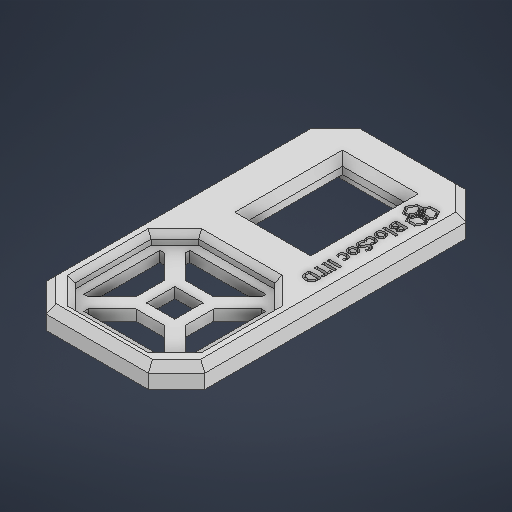
# Autodesk Inventor part: front_pannel_v3
Saved by Autodesk Inventor 2026.2 (Build 302298010, 298A)
## iProperties
Created: 2026-08-06
Part Number: front_pannel_v3
Material: Generic
Document SubType Name: Modeling
Designer: Kugelblitz
Density: 1 g/cm^3
Appearance: Default
Author: Kugelblitz
Autodesk Inventor part; units mm, degrees
ref_plane "YZ Plane" through (0, 0, 0) normal (1, 0, 0) x (0, 1, 0)
ref_plane "XZ Plane" through (0, 0, 0) normal (0, 1, 0) x (-1, 0, 0)
ref_plane "XY Plane" through (0, 0, 0) normal (0, 0, 1) x (1, 0, 0)
sketch "Sketch1" plane through (0, 0, 0) normal (0, 1, 0) x (-1, 0, 0)
  line L0 (22.5, 22) -> (-22.5, 22)
  line L1 (-22.5, 22) -> (-22.5, -68)
  line L2 (-22.5, -68) -> (22.5, -68)
  line L3 (22.5, -68) -> (22.5, 22)
  line L4 (22.5, -23) -> (-22.5, -23)
  line L5 (-22.5, 14) -> (-14.5, 22)
  line L6 (22.5, 14) -> (14.5, 22)
  line L7 (0, -25.7487) -> (0, 24.7487) construction
  line L8 (-24.7487, 0) -> (24.7487, 0) construction
  line L9 (-14.5, -68) -> (-22.5, -60)
  line L10 (22.5, -60) -> (14.5, -68)
  point P0 (0, 0)
  point P1 (15.5, -0.5)
  point P2 (0, -23)
  point P3 (0, 0)
  point P4 (0, -0.5)
  dimension "d3" = 7
  dimension "d11" = 35
  dimension "d14" = 8
  dimension "d15" = 135
  dimension "d16" = 8
  dimension "d21" = 135
  dimension "d22" = 8
  dimension "d23" = 8
  dimension "d68" = 22
  dimension "d69" = 45
  dimension "d70" = 45
  dimension "d71" = 45
  dimension "d72" = 22.5
  dimension "d73" = 22.5
  constraints: 22 end point, 9 point on line, 6 midpoint, 4 perpendicular, 2 parallel, 1 horizontal
  measures "d3" distance from line of point (15.5, -0.5) L3
  measures "d11" distance of L8.start L7.end
  measures "d14" horizontal distance of L5.start L5.end
  measures "d15" angle of L1 L5
  measures "d16" horizontal distance of L6.start L6.end
  measures "d21" angle of L2 L9
  measures "d22" distance from line of L1 L9.start
  measures "d23" distance of L2.end L10.end
  measures "d68" distance from line of L0 point (0, 0)
  measures "d69" distance between parallel lines of L0 L4
  measures "d70" distance between parallel lines of L4 L2
  measures "d71" distance between parallel lines of L3 L1
  measures "d72" distance from line of L3 point (0, -0.5)
  measures "d73" distance from line of L0 point (0, -0.5)
extrude "Extrusion1" add sketch "Sketch1" along normal blind 4 and the other way blind 2 contours L6 L3 L4 L1 L5 L0 | L3 L10 L2 L9 L1 L4
chamfer "Chamfer2" distance 2 angle 45 8 edges at (-22.5, 4, -23) (-18.5, 4, -64) (0, 4, -68) (18.5, 4, -64) (22.5, 4, -23) (18.5, 4, 18) (0, 4, 22) (-18.5, 4, 18)
sketch "Sketch12" plane through (0, 4, 0) normal (0, 1, 0) x (1, 0, 0)
  line L0 (17.5, 17.5) -> (-17.5, 17.5)
  line L1 (-17.5, 17.5) -> (-17.5, -17.5)
  line L2 (-17.5, -17.5) -> (17.5, -17.5)
  line L3 (17.5, -17.5) -> (17.5, 17.5)
  line L4 (17.5, 17.5) -> (-17.5, -17.5) construction
  line L5 (-17.5, 17.5) -> (17.5, -17.5) construction
  line L6 (-28.2843, 0) -> (0, -28.2843)
  line L7 (0, -28.2843) -> (28.2843, 0)
  line L8 (28.2843, 0) -> (0, 28.2843)
  line L9 (0, 28.2843) -> (-28.2843, 0)
  line L10 (-28.2843, 0) -> (28.2843, 0) construction
  line L11 (0, -28.2843) -> (0, 28.2843) construction
  point P0 (0, 0)
  point P1 (-10.7843, 17.5)
  point P2 (-17.5, 10.7843)
  point P3 (-17.5, -10.7843)
  point P4 (-10.7843, -17.5)
  point P5 (10.7843, -17.5)
  point P6 (17.5, -10.7843)
  point P7 (17.5, 10.7843)
  point P8 (10.7843, 17.5)
  dimension "d74" = 35
  dimension "d75" = 35
  dimension "d76" = 40
  dimension "d77" = 40
  constraints: 24 end point, 4 midpoint, 4 parallel, 2 perpendicular, 1 horizontal
  measures "d74" distance of L2.end L1.end
  measures "d75" distance of L1.end L0.end
  measures "d76" distance of L6.start L6.end
  measures "d77" distance of L7.end L6.end
extrude "Extrusion6" cut sketch "Sketch12" against normal blind 3 contours L8 L3 L7 L2 L6 L1 L9 L0
sketch "Sketch13" plane through (0, 1, 0) normal (0, 1, 0) x (1, 0, 0)
  line L0 (-4, 4) -> (4, 4)
  line L1 (4, 4) -> (4, -4)
  line L2 (4, -4) -> (-4, -4)
  line L3 (-4, -4) -> (-4, 4)
  line L4 (-4, 4) -> (4, -4) construction
  line L5 (4, 4) -> (-4, -4) construction
  line L6 (4, -7) -> (-4, -7)
  line L7 (-4, -7) -> (-10.7843, -13.7843)
  line L8 (10.7843, -13.7843) -> (4, -7)
  line L9 (17.5, -10.7843) -> (10.7843, -17.5) projected
  line L10 (10.7843, -13.7843) -> (10.7843, -15)
  line L11 (10.7843, -15) -> (-10.7843, -15)
  line L12 (-10.7843, -15) -> (-10.7843, -13.7843)
  line L13 (10.7843, -17.5) -> (-10.7843, -17.5) projected
  line L14 (7, 4) -> (7, -4)
  line L15 (7, -4) -> (13.7843, -10.7843)
  line L16 (15, -10.7843) -> (13.7843, -10.7843)
  line L17 (15, 10.7843) -> (15, -10.7843)
  line L18 (13.7843, 10.7843) -> (15, 10.7843)
  line L19 (13.7843, 10.7843) -> (7, 4)
  line L20 (-4, 7) -> (4, 7)
  line L21 (4, 7) -> (10.7843, 13.7843)
  line L22 (10.7843, 15) -> (10.7843, 13.7843)
  line L23 (-10.7843, 15) -> (10.7843, 15)
  line L24 (-10.7843, 13.7843) -> (-10.7843, 15)
  line L25 (-10.7843, 13.7843) -> (-4, 7)
  line L26 (-7, -4) -> (-7, 4)
  line L27 (-7, 4) -> (-13.7843, 10.7843)
  line L28 (-15, 10.7843) -> (-13.7843, 10.7843)
  line L29 (-15, -10.7843) -> (-15, 10.7843)
  line L30 (-13.7843, -10.7843) -> (-15, -10.7843)
  line L31 (-13.7843, -10.7843) -> (-7, -4)
  point P0 (0, 0)
  point P1 (0, -4)
  point P2 (0, -7)
  point P3 (7, 0)
  point P4 (0, 7)
  point P5 (-7, 0)
  dimension "d80" = 8
  dimension "d81" = 8
  dimension "d82" = 8
  dimension "d83" = 0
  dimension "d84" = 3
  dimension "d85" = 8
  dimension "d86" = 0
  dimension "d87" = 0
  dimension "d90" = 360
  constraints: 60 end point, 5 perpendicular, 4 midpoint, 2 horizontal, 2 parallel, 1 vertical, 53 other
  measures "d80" distance of L1.end L2.end
  measures "d81" distance of L0.end L1.end
  measures "d82" distance of L6.start L6.end
  measures "d83" horizontal distance of point (0, -4) point (0, -7)
  measures "d84" distance between parallel lines of L6 L2
  measures "d85" distance between parallel lines of L6 L11
  measures "d86" horizontal distance of L9.end L10.end
  measures "d87" horizontal distance of L13.end L11.end
extrude "Extrusion7" cut sketch "Sketch13" against normal through all
sketch "Sketch14" plane through (0, 4, 0) normal (0, 1, 0) x (1, 0, 0)
  line L0 (8.75, 56.25) -> (-8.75, 56.25)
  line L1 (-8.75, 56.25) -> (-8.75, 29.75)
  line L2 (-8.75, 29.75) -> (8.75, 29.75)
  line L3 (8.75, 29.75) -> (8.75, 56.25)
  line L4 (-13.6716, 66) -> (13.6716, 66) projected
  line L5 (0, 66) -> (0, 17.5)
  line L6 (-10.7843, 17.5) -> (10.7843, 17.5) projected
  point P0 (0, 0)
  point P1 (0, 66)
  point P2 (0, 56.25)
  point P3 (8.75, 43)
  point P4 (0, 66)
  dimension "d94" = 17.5
  dimension "d95" = 26.5
  dimension "d96" = 0
  dimension "d97" = 23
  dimension "d98" = 0
  constraints: 10 end point, 6 midpoint, 2 parallel, 1 horizontal, 1 perpendicular, 1 vertical
  measures "d94" distance of L1.end L2.end
  measures "d95" distance of L2.end L0.start
  measures "d96" horizontal distance of point (0, 66) point (0, 56.25)
  measures "d97" distance from line of L4 point (8.75, 43)
  measures "d98" distance from line of point (0, 66) L5
extrude "Extrusion8" cut sketch "Sketch14" against normal blind 10
chamfer "Chamfer4" distance 1.5 angle 45 8 edges at (17.5, 4, 0) (14.1421, 4, -14.1421) (0, 4, -17.5) (-14.1421, 4, -14.1421) (-17.5, 4, 0) (-14.1421, 4, 14.1421) (0, 4, 17.5) (14.1421, 4, 14.1421)
chamfer "Chamfer5" distance 2 angle 45 4 edges at (8.75, 4, -43) (0, 4, -56.25) (-8.75, 4, -43) (0, 4, -29.75)
sketch "Sketch15" plane through (0, -2, 0) normal (0, -1, 0) x (1, 0, 0)
  line L0 (14, -29) -> (-14, -29)
  line L1 (-14, -29) -> (-14, -57)
  line L2 (-14, -57) -> (14, -57)
  line L3 (14, -57) -> (14, -29)
  line L4 (8.75, -56.25) -> (-8.75, -56.25) projected
  line L5 (8.75, -29.75) -> (8.75, -56.25) projected
  point P0 (0, 0)
  point P1 (0, -57)
  point P2 (0, -56.25)
  point P3 (8.75, -43)
  point P4 (14, -43)
  dimension "d107" = 0
  dimension "d108" = 0
  dimension "d109" = 28
  dimension "d110" = 28
  constraints: 8 end point, 4 midpoint, 2 parallel, 1 horizontal, 1 perpendicular
  measures "d107" horizontal distance of point (0, -57) point (0, -56.25)
  measures "d108" vertical distance of point (8.75, -43) point (14, -43)
  measures "d109" distance of L2.end L0.start
  measures "d110" distance of L1.end L2.end
extrude "Extrusion9" cut sketch "Sketch15" against normal blind 2
sketch "Sketch17" plane through (0, 4, 0) normal (0, 1, 0) x (1, 0, 0)
  line L0 (17.9346, 48.8212) -> (17.9346, 19.4643) construction
  line L1 (17.9346, 19.4643) -> (10.0297, 19.4643) construction
  line L2 (10.0297, 19.4643) -> (10.0297, 48.8212) construction
  line L3 (10.0297, 48.8212) -> (17.9346, 48.8212) construction
  line L4 (20.5, 59.1716) -> (20.5, -13.1716) projected
  line L5 (15.6198, 52.5504) -> (14.3698, 54.7154)
  line L6 (14.3698, 54.7154) -> (15.6198, 56.8805)
  line L7 (15.6198, 56.8805) -> (18.1198, 56.8805)
  line L8 (18.1198, 56.8805) -> (19.3698, 54.7154)
  line L9 (19.3698, 54.7154) -> (18.1198, 52.5504)
  line L10 (18.1198, 52.5504) -> (15.6198, 52.5504)
  line L11 (15.9662, 56.2805) -> (17.7734, 56.2805)
  line L12 (17.7734, 56.2805) -> (18.677, 54.7154)
  line L13 (18.677, 54.7154) -> (17.7734, 53.1504)
  line L14 (17.7734, 53.1504) -> (15.9662, 53.1504)
  line L15 (15.9662, 53.1504) -> (15.0627, 54.7154)
  line L16 (15.0627, 54.7154) -> (15.9662, 56.2805)
  line L17 (15.6198, 49.8203) -> (14.3698, 51.9853)
  line L18 (14.3698, 51.9853) -> (15.6198, 54.1504)
  line L19 (15.6198, 54.1504) -> (18.1198, 54.1504)
  line L20 (18.1198, 54.1504) -> (19.3698, 51.9853)
  line L21 (19.3698, 51.9853) -> (18.1198, 49.8203)
  line L22 (18.1198, 49.8203) -> (15.6198, 49.8203)
  line L23 (15.9662, 53.5504) -> (17.7734, 53.5504)
  line L24 (17.7734, 53.5504) -> (18.677, 51.9853)
  line L25 (18.677, 51.9853) -> (17.7734, 50.4203)
  line L26 (17.7734, 50.4203) -> (15.9662, 50.4203)
  line L27 (15.9662, 50.4203) -> (15.0627, 51.9853)
  line L28 (15.0627, 51.9853) -> (15.9662, 53.5504)
  line L29 (13.2555, 51.1853) -> (12.0055, 53.3504)
  line L30 (12.0055, 53.3504) -> (13.2555, 55.5154)
  line L31 (13.2555, 55.5154) -> (15.7555, 55.5154)
  line L32 (15.7555, 55.5154) -> (17.0055, 53.3504)
  line L33 (17.0055, 53.3504) -> (15.7555, 51.1853)
  line L34 (15.7555, 51.1853) -> (13.2555, 51.1853)
  line L35 (13.6019, 54.9154) -> (15.4091, 54.9154)
  line L36 (15.4091, 54.9154) -> (16.3127, 53.3504)
  line L37 (16.3127, 53.3504) -> (15.4091, 51.7853)
  line L38 (15.4091, 51.7853) -> (13.6019, 51.7853)
  line L39 (13.6019, 51.7853) -> (12.6983, 53.3504)
  line L40 (12.6983, 53.3504) -> (13.6019, 54.9154)
  spline S0 degree 2 poles (15.2299, 45.9161) (15.0426, 45.9161) (14.7403, 46.0179) (14.5102, 46.1987) (14.3426, 46.4485) (14.2375, 46.7508) (14.1849, 47.0926) (14.1849, 47.3029) knots 0 0 0 1 2 3 4 5 6 6 6
  line L41 (14.1849, 47.3029) -> (14.1849, 48.2297)
  spline S1 degree 2 poles (14.1849, 48.2297) (14.1849, 48.3184) (14.29, 48.44) (14.4083, 48.44) knots 0 0 0 1 2 2 2
  line L42 (14.4083, 48.44) -> (17.445, 48.44)
  spline S2 degree 2 poles (17.445, 48.44) (17.5633, 48.44) (17.6684, 48.3184) (17.6684, 48.2297) knots 0 0 0 1 2 2 2
  line L43 (17.6684, 48.2297) -> (17.6684, 47.3555)
  spline S3 degree 2 poles (17.6684, 47.3555) (17.6684, 47.0334) (17.56, 46.5898) (17.3431, 46.2841) (17.0079, 46.1231) (16.7811, 46.1231) knots 0 0 0 1 2 3 4 4 4
  spline S4 degree 2 poles (16.7811, 46.1231) (16.6562, 46.1231) (16.4328, 46.1888) (16.2487, 46.3104) (16.1074, 46.4912) (16.0647, 46.6095) knots 0 0 0 1 2 3 4 4 4
  spline S5 degree 2 poles (16.0647, 46.6095) (16.0384, 46.4583) (15.9037, 46.2086) (15.6933, 46.0245) (15.4074, 45.9161) (15.2299, 45.9161) knots 0 0 0 1 2 3 4 4 4
  spline S6 degree 2 poles (15.2069, 46.6522) (15.3253, 46.6522) (15.5159, 46.7344) (15.6473, 46.8888) (15.7163, 47.132) (15.7163, 47.3259) knots 0 0 0 1 2 3 4 4 4
  line L44 (15.7163, 47.3259) -> (15.7163, 47.7466)
  line L45 (15.7163, 47.7466) -> (14.7271, 47.7466)
  line L46 (14.7271, 47.7466) -> (14.7271, 47.2339)
  spline S7 degree 2 poles (14.7271, 47.2339) (14.7271, 47.086) (14.7896, 46.8855) (14.9112, 46.7344) (15.0886, 46.6522) (15.2069, 46.6522) knots 0 0 0 1 2 3 4 4 4
  spline S8 degree 2 poles (16.6957, 46.8297) (16.8008, 46.8297) (16.9684, 46.8954) (17.0802, 47.0236) (17.1393, 47.2208) (17.1393, 47.3884) knots 0 0 0 1 2 3 4 4 4
  line L47 (17.1393, 47.3884) -> (17.1393, 47.7466)
  line L48 (17.1393, 47.7466) -> (16.2323, 47.7466)
  line L49 (16.2323, 47.7466) -> (16.2323, 47.3489)
  spline S9 degree 2 poles (16.2323, 47.3489) (16.2323, 47.1945) (16.3046, 47.0104) (16.4328, 46.8888) (16.6037, 46.8297) (16.6957, 46.8297) knots 0 0 0 1 2 3 4 4 4
  spline S10 degree 2 poles (14.2769, 44.7132) (14.2506, 44.7132) (14.2079, 44.7461) (14.1816, 44.825) (14.1684, 44.9532) (14.1684, 45.0517) knots 0 0 0 1 2 3 4 4 4
  spline S11 degree 2 poles (14.1684, 45.0517) (14.1684, 45.1503) (14.1816, 45.2785) (14.2079, 45.3574) (14.2506, 45.3902) (14.2769, 45.3902) knots 0 0 0 1 2 3 4 4 4
  line L50 (14.2769, 45.3902) -> (17.8196, 45.3902)
  spline S12 degree 2 poles (17.8196, 45.3902) (17.8459, 45.3902) (17.8886, 45.3574) (17.9182, 45.2785) (17.9346, 45.1503) (17.9346, 45.0517) knots 0 0 0 1 2 3 4 4 4
  spline S13 degree 2 poles (17.9346, 45.0517) (17.9346, 44.9532) (17.9182, 44.825) (17.8886, 44.7461) (17.8459, 44.7132) (17.8196, 44.7132) knots 0 0 0 1 2 3 4 4 4
  line L51 (17.8196, 44.7132) -> (14.2769, 44.7132)
  spline S14 degree 2 poles (15.4994, 41.6076) (15.1938, 41.6076) (14.6877, 41.7686) (14.3229, 42.0973) (14.1224, 42.5935) (14.1224, 42.9255) knots 0 0 0 1 2 3 4 4 4
  spline S15 degree 2 poles (14.1224, 42.9255) (14.1224, 43.2442) (14.2999, 43.7175) (14.6384, 44.0297) (15.1346, 44.1809) (15.4534, 44.1809) knots 0 0 0 1 2 3 4 4 4
  spline S16 degree 2 poles (15.4534, 44.1809) (15.7591, 44.1809) (16.2684, 44.0165) (16.6299, 43.6879) (16.8304, 43.1949) (16.8304, 42.863) knots 0 0 0 1 2 3 4 4 4
  spline S17 degree 2 poles (16.8304, 42.863) (16.8304, 42.5409) (16.6562, 42.0677) (16.3177, 41.7588) (15.8215, 41.6076) (15.4994, 41.6076) knots 0 0 0 1 2 3 4 4 4
  spline S18 degree 2 poles (15.4731, 42.3043) (15.6506, 42.3043) (15.9497, 42.3602) (16.1699, 42.4949) (16.2947, 42.7184) (16.2947, 42.8893) knots 0 0 0 1 2 3 4 4 4
  spline S19 degree 2 poles (16.2947, 42.8893) (16.2947, 43.0405) (16.183, 43.2672) (15.9727, 43.4118) (15.6736, 43.4841) (15.483, 43.4841) knots 0 0 0 1 2 3 4 4 4
  spline S20 degree 2 poles (15.483, 43.4841) (15.3055, 43.4841) (15.0065, 43.425) (14.7863, 43.2935) (14.6647, 43.0668) (14.6647, 42.8992) knots 0 0 0 1 2 3 4 4 4
  spline S21 degree 2 poles (14.6647, 42.8992) (14.6647, 42.7447) (14.7764, 42.5212) (14.9835, 42.3733) (15.2825, 42.3043) (15.4731, 42.3043) knots 0 0 0 1 2 3 4 4 4
  spline S22 degree 2 poles (14.6581, 39.2546) (14.5891, 39.2546) (14.4938, 39.2611) (14.4281, 39.2776) (14.3886, 39.294) (14.3262, 39.3597) (14.2375, 39.5142) (14.1684, 39.7147) (14.1257, 39.948) (14.1257, 40.0729) knots 0 0 0 1 2 3 4 5 6 7 8 8 8
  spline S23 degree 2 poles (14.1257, 40.0729) (14.1257, 40.3489) (14.2966, 40.7794) (14.6351, 41.0686) (15.1182, 41.2165) (15.4337, 41.2165) knots 0 0 0 1 2 3 4 4 4
  spline S24 degree 2 poles (15.4337, 41.2165) (15.7919, 41.2165) (16.3177, 41.0358) (16.6628, 40.7137) (16.8304, 40.2733) (16.8304, 40.0071) knots 0 0 0 1 2 3 4 4 4
  spline S25 degree 2 poles (16.8304, 40.0071) (16.8304, 39.902) (16.791, 39.6917) (16.7285, 39.5142) (16.6464, 39.3696) (16.5872, 39.3104) (16.5478, 39.2874) (16.4821, 39.2743) (16.3868, 39.2644) (16.321, 39.2644) knots 0 0 0 1 2 3 4 5 6 7 8 8 8
  spline S26 degree 2 poles (16.321, 39.2644) (16.1633, 39.2644) (16.0384, 39.3203) (16.0384, 39.363) knots 0 0 0 1 2 2 2
  spline S27 degree 2 poles (16.0384, 39.363) (16.0384, 39.409) (16.114, 39.5109) (16.206, 39.6489) (16.2816, 39.8428) (16.2816, 39.9776) knots 0 0 0 1 2 3 4 4 4
  spline S28 degree 2 poles (16.2816, 39.9776) (16.2816, 40.2438) (15.8741, 40.5231) (15.4797, 40.5231) knots 0 0 0 1 2 2 2
  spline S29 degree 2 poles (15.4797, 40.5231) (15.2858, 40.5231) (14.99, 40.4541) (14.7896, 40.3161) (14.691, 40.109) (14.691, 39.971) knots 0 0 0 1 2 3 4 4 4
  spline S30 degree 2 poles (14.691, 39.971) (14.691, 39.8297) (14.7731, 39.6292) (14.8783, 39.478) (14.9605, 39.3762) (14.9605, 39.34) knots 0 0 0 1 2 3 4 4 4
  spline S31 degree 2 poles (14.9605, 39.34) (14.9605, 39.317) (14.9342, 39.2841) (14.8619, 39.2644) (14.7468, 39.2546) (14.6581, 39.2546) knots 0 0 0 1 2 3 4 4 4
  spline S32 degree 2 poles (15.2299, 36.6583) (14.9539, 36.6583) (14.5398, 36.8621) (14.2637, 37.2137) (14.1224, 37.6804) (14.1224, 37.9466) knots 0 0 0 1 2 3 4 4 4
  spline S33 degree 2 poles (14.1224, 37.9466) (14.1224, 38.1273) (14.1816, 38.4363) (14.267, 38.6729) (14.3591, 38.8339) (14.4281, 38.9029) (14.5595, 38.9325) (14.6844, 38.9325) knots 0 0 0 1 2 3 4 5 6 6 6
  spline S34 degree 2 poles (14.6844, 38.9325) (14.7666, 38.9325) (14.8816, 38.9226) (14.9506, 38.8963) (14.9802, 38.8569) (14.9802, 38.8306) knots 0 0 0 1 2 3 4 4 4
  spline S35 degree 2 poles (14.9802, 38.8306) (14.9802, 38.7912) (14.8914, 38.6564) (14.783, 38.4395) (14.6943, 38.1405) (14.6943, 37.9466) knots 0 0 0 1 2 3 4 4 4
  spline S36 degree 2 poles (14.6943, 37.9466) (14.6943, 37.8151) (14.7567, 37.6114) (14.8684, 37.4701) (15.036, 37.3945) (15.1379, 37.3945) knots 0 0 0 1 2 3 4 4 4
  spline S37 degree 2 poles (15.1379, 37.3945) (15.2562, 37.3945) (15.4271, 37.5226) (15.5586, 37.7297) (15.6736, 37.9926) (15.8018, 38.2752) (15.9661, 38.5381) (16.1961, 38.7452) (16.5083, 38.8733) (16.7253, 38.8733) knots 0 0 0 1 2 3 4 5 6 7 8 8 8
  spline S38 degree 2 poles (16.7253, 38.8733) (16.9783, 38.8733) (17.3562, 38.686) (17.606, 38.3738) (17.7309, 37.9433) (17.7309, 37.7034) knots 0 0 0 1 2 3 4 4 4
  spline S39 degree 2 poles (17.7309, 37.7034) (17.7309, 37.5818) (17.6947, 37.332) (17.629, 37.1184) (17.5468, 36.9508) (17.4943, 36.8949) (17.4581, 36.8785) (17.3957, 36.8654) (17.3004, 36.8588) (17.2314, 36.8588) knots 0 0 0 1 2 3 4 5 6 7 8 8 8
  spline S40 degree 2 poles (17.2314, 36.8588) (17.1525, 36.8588) (17.044, 36.8654) (16.975, 36.8851) (16.9422, 36.9212) (16.9422, 36.9508) knots 0 0 0 1 2 3 4 4 4
  spline S41 degree 2 poles (16.9422, 36.9508) (16.9422, 36.9804) (17.0177, 37.1086) (17.1065, 37.2992) (17.1788, 37.5456) (17.1788, 37.6935) knots 0 0 0 1 2 3 4 4 4
  spline S42 degree 2 poles (17.1788, 37.6935) (17.1788, 37.8086) (17.1229, 37.9827) (17.021, 38.0978) (16.883, 38.1536) (16.8041, 38.1536) knots 0 0 0 1 2 3 4 4 4
  spline S43 degree 2 poles (16.8041, 38.1536) (16.6891, 38.1536) (16.5182, 38.0287) (16.3868, 37.8151) (16.2717, 37.5456) (16.1436, 37.2663) (15.9792, 36.9968) (15.7492, 36.7865) (15.4403, 36.6583) (15.2299, 36.6583) knots 0 0 0 1 2 3 4 5 6 7 8 8 8
  spline S44 degree 2 poles (15.4994, 33.7302) (15.1938, 33.7302) (14.6877, 33.8912) (14.3229, 34.2198) (14.1224, 34.7161) (14.1224, 35.048) knots 0 0 0 1 2 3 4 4 4
  spline S45 degree 2 poles (14.1224, 35.048) (14.1224, 35.3668) (14.2999, 35.84) (14.6384, 36.1522) (15.1346, 36.3034) (15.4534, 36.3034) knots 0 0 0 1 2 3 4 4 4
  spline S46 degree 2 poles (15.4534, 36.3034) (15.7591, 36.3034) (16.2684, 36.1391) (16.6299, 35.8104) (16.8304, 35.3175) (16.8304, 34.9855) knots 0 0 0 1 2 3 4 4 4
  spline S47 degree 2 poles (16.8304, 34.9855) (16.8304, 34.6635) (16.6562, 34.1902) (16.3177, 33.8813) (15.8215, 33.7302) (15.4994, 33.7302) knots 0 0 0 1 2 3 4 4 4
  spline S48 degree 2 poles (15.4731, 34.4269) (15.6506, 34.4269) (15.9497, 34.4827) (16.1699, 34.6175) (16.2947, 34.8409) (16.2947, 35.0118) knots 0 0 0 1 2 3 4 4 4
  spline S49 degree 2 poles (16.2947, 35.0118) (16.2947, 35.163) (16.183, 35.3898) (15.9727, 35.5344) (15.6736, 35.6067) (15.483, 35.6067) knots 0 0 0 1 2 3 4 4 4
  spline S50 degree 2 poles (15.483, 35.6067) (15.3055, 35.6067) (15.0065, 35.5475) (14.7863, 35.4161) (14.6647, 35.1893) (14.6647, 35.0217) knots 0 0 0 1 2 3 4 4 4
  spline S51 degree 2 poles (14.6647, 35.0217) (14.6647, 34.8672) (14.7764, 34.6438) (14.9835, 34.4959) (15.2825, 34.4269) (15.4731, 34.4269) knots 0 0 0 1 2 3 4 4 4
  spline S52 degree 2 poles (14.6581, 31.3771) (14.5891, 31.3771) (14.4938, 31.3837) (14.4281, 31.4001) (14.3886, 31.4165) (14.3262, 31.4823) (14.2375, 31.6367) (14.1684, 31.8372) (14.1257, 32.0705) (14.1257, 32.1954) knots 0 0 0 1 2 3 4 5 6 7 8 8 8
  spline S53 degree 2 poles (14.1257, 32.1954) (14.1257, 32.4715) (14.2966, 32.902) (14.6351, 33.1912) (15.1182, 33.3391) (15.4337, 33.3391) knots 0 0 0 1 2 3 4 4 4
  spline S54 degree 2 poles (15.4337, 33.3391) (15.7919, 33.3391) (16.3177, 33.1583) (16.6628, 32.8363) (16.8304, 32.3959) (16.8304, 32.1297) knots 0 0 0 1 2 3 4 4 4
  spline S55 degree 2 poles (16.8304, 32.1297) (16.8304, 32.0245) (16.791, 31.8142) (16.7285, 31.6367) (16.6464, 31.4921) (16.5872, 31.433) (16.5478, 31.41) (16.4821, 31.3968) (16.3868, 31.387) (16.321, 31.387) knots 0 0 0 1 2 3 4 5 6 7 8 8 8
  spline S56 degree 2 poles (16.321, 31.387) (16.1633, 31.387) (16.0384, 31.4428) (16.0384, 31.4855) knots 0 0 0 1 2 2 2
  spline S57 degree 2 poles (16.0384, 31.4855) (16.0384, 31.5316) (16.114, 31.6334) (16.206, 31.7715) (16.2816, 31.9654) (16.2816, 32.1001) knots 0 0 0 1 2 3 4 4 4
  spline S58 degree 2 poles (16.2816, 32.1001) (16.2816, 32.3663) (15.8741, 32.6456) (15.4797, 32.6456) knots 0 0 0 1 2 2 2
  spline S59 degree 2 poles (15.4797, 32.6456) (15.2858, 32.6456) (14.99, 32.5766) (14.7896, 32.4386) (14.691, 32.2316) (14.691, 32.0935) knots 0 0 0 1 2 3 4 4 4
  spline S60 degree 2 poles (14.691, 32.0935) (14.691, 31.9522) (14.7731, 31.7517) (14.8783, 31.6006) (14.9605, 31.4987) (14.9605, 31.4625) knots 0 0 0 1 2 3 4 4 4
  spline S61 degree 2 poles (14.9605, 31.4625) (14.9605, 31.4395) (14.9342, 31.4067) (14.8619, 31.387) (14.7468, 31.3771) (14.6581, 31.3771) knots 0 0 0 1 2 3 4 4 4
  spline S62 degree 2 poles (14.2802, 28.8893) (14.2539, 28.8893) (14.2112, 28.9255) (14.1849, 29.0043) (14.1684, 29.1391) (14.1684, 29.2442) knots 0 0 0 1 2 3 4 4 4
  spline S63 degree 2 poles (14.1684, 29.2442) (14.1684, 29.3461) (14.1849, 29.4841) (14.2112, 29.563) (14.2539, 29.5992) (14.2802, 29.5992) knots 0 0 0 1 2 3 4 4 4
  line L52 (14.2802, 29.5992) -> (17.5731, 29.5992)
  spline S64 degree 2 poles (17.5731, 29.5992) (17.5994, 29.5992) (17.6422, 29.563) (17.6684, 29.4809) (17.6849, 29.3461) (17.6849, 29.2442) knots 0 0 0 1 2 3 4 4 4
  spline S65 degree 2 poles (17.6849, 29.2442) (17.6849, 29.1391) (17.6684, 29.0043) (17.6422, 28.9255) (17.5994, 28.8893) (17.5731, 28.8893) knots 0 0 0 1 2 3 4 4 4
  line L53 (17.5731, 28.8893) -> (14.2802, 28.8893)
  spline S66 degree 2 poles (14.2802, 27.4203) (14.2539, 27.4203) (14.2112, 27.4564) (14.1849, 27.5353) (14.1684, 27.6701) (14.1684, 27.7752) knots 0 0 0 1 2 3 4 4 4
  spline S67 degree 2 poles (14.1684, 27.7752) (14.1684, 27.8771) (14.1849, 28.0151) (14.2112, 28.094) (14.2539, 28.1302) (14.2802, 28.1302) knots 0 0 0 1 2 3 4 4 4
  line L54 (14.2802, 28.1302) -> (17.5731, 28.1302)
  spline S68 degree 2 poles (17.5731, 28.1302) (17.5994, 28.1302) (17.6422, 28.094) (17.6684, 28.0118) (17.6849, 27.8771) (17.6849, 27.7752) knots 0 0 0 1 2 3 4 4 4
  spline S69 degree 2 poles (17.6849, 27.7752) (17.6849, 27.6701) (17.6684, 27.5353) (17.6422, 27.4564) (17.5994, 27.4203) (17.5731, 27.4203) knots 0 0 0 1 2 3 4 4 4
  line L55 (17.5731, 27.4203) -> (14.2802, 27.4203)
  spline S70 degree 2 poles (17.3792, 24.3475) (17.3004, 24.3475) (17.1886, 24.3607) (17.1229, 24.387) (17.09, 24.4297) (17.09, 24.4527) knots 0 0 0 1 2 3 4 4 4
  line L56 (17.09, 24.4527) -> (17.09, 25.3236)
  line L57 (17.09, 25.3236) -> (14.2802, 25.3236)
  spline S71 degree 2 poles (14.2802, 25.3236) (14.2539, 25.3236) (14.2112, 25.3597) (14.1849, 25.4386) (14.1684, 25.5766) (14.1684, 25.6785) knots 0 0 0 1 2 3 4 4 4
  spline S72 degree 2 poles (14.1684, 25.6785) (14.1684, 25.7804) (14.1849, 25.9184) (14.2112, 25.9973) (14.2539, 26.0334) (14.2802, 26.0334) knots 0 0 0 1 2 3 4 4 4
  line L58 (14.2802, 26.0334) -> (17.09, 26.0334)
  line L59 (17.09, 26.0334) -> (17.09, 26.9043)
  spline S73 degree 2 poles (17.09, 26.9043) (17.09, 26.9306) (17.1229, 26.9701) (17.1886, 26.9963) (17.3004, 27.0095) (17.3792, 27.0095) knots 0 0 0 1 2 3 4 4 4
  spline S74 degree 2 poles (17.3792, 27.0095) (17.4581, 27.0095) (17.5731, 26.9963) (17.6389, 26.9701) (17.6684, 26.9306) (17.6684, 26.9043) knots 0 0 0 1 2 3 4 4 4
  line L60 (17.6684, 26.9043) -> (17.6684, 24.4527)
  spline S75 degree 2 poles (17.6684, 24.4527) (17.6684, 24.4297) (17.6389, 24.387) (17.5731, 24.3607) (17.4581, 24.3475) (17.3792, 24.3475) knots 0 0 0 1 2 3 4 4 4
  spline S76 degree 2 poles (15.9792, 21.0348) (15.4994, 21.0348) (14.8191, 21.2846) (14.3853, 21.7546) (14.1849, 22.425) (14.1849, 22.8884) knots 0 0 0 1 2 3 4 4 4
  line L61 (14.1849, 22.8884) -> (14.1849, 23.7198)
  spline S77 degree 2 poles (14.1849, 23.7198) (14.1849, 23.8086) (14.29, 23.9302) (14.4083, 23.9302) knots 0 0 0 1 2 2 2
  line L62 (14.4083, 23.9302) -> (17.445, 23.9302)
  spline S78 degree 2 poles (17.445, 23.9302) (17.5633, 23.9302) (17.6684, 23.8086) (17.6684, 23.7198) knots 0 0 0 1 2 2 2
  line L63 (17.6684, 23.7198) -> (17.6684, 22.8259)
  spline S79 degree 2 poles (17.6684, 22.8259) (17.6684, 22.3593) (17.4515, 21.7118) (17.021, 21.2649) (16.3933, 21.0348) (15.9792, 21.0348) knots 0 0 0 1 2 3 4 4 4
  spline S80 degree 2 poles (15.953, 21.7677) (16.1994, 21.7677) (16.6267, 21.8827) (16.9389, 22.1391) (17.113, 22.54) (17.113, 22.8654) knots 0 0 0 1 2 3 4 4 4
  line L64 (17.113, 22.8654) -> (17.113, 23.2236)
  line L65 (17.113, 23.2236) -> (14.7436, 23.2236)
  line L66 (14.7436, 23.2236) -> (14.7436, 22.8555)
  spline S81 degree 2 poles (14.7436, 22.8555) (14.7436, 22.563) (14.8947, 22.1654) (15.1971, 21.8992) (15.6506, 21.7677) (15.953, 21.7677) knots 0 0 0 1 2 3 4 4 4
  point P0 (0, 0)
  point P1 (16.8698, 54.7154)
  point P2 (16.8698, 54.7154)
  point P3 (16.8698, 51.9853)
  point P4 (16.8698, 51.9853)
  point P5 (16.8698, 54.1504)
  point P6 (16.8698, 52.5504)
  point P7 (14.5055, 53.3504)
  point P8 (14.5055, 53.3504)
  point P9 (14.5055, 50.1125)
  point P10 (14.5055, 51.1853)
  point P11 (18.2353, 52.7504)
  point P12 (15.5245, 51.1853)
  point P13 (16.5436, 52.5504)
  point P14 (17.8889, 53.3504)
  point P15 (16.89, 53.1504)
  point P16 (16.89, 53.5504)
  point P17 (15.5044, 53.9504)
  point P18 (15.1781, 54.9154)
  point P19 (15.8508, 54.1504)
  point P20 (15.5044, 52.7504)
  point P21 (15.8508, 52.5504)
  point P22 (15.1781, 51.7853)
  point P23 (15.158, 53.3504)
  point P24 (14.4853, 51.7853)
  point P25 (14.4853, 54.9154)
  point P26 (18.5817, 53.3504)
  point P27 (14.8317, 55.5154)
  point P28 (14.8317, 51.1853)
  point P29 (15.8508, 53.3504)
  point P30 (16.1972, 53.5504)
  point P31 (16.1972, 53.1504)
  point P32 (18.2353, 53.9504)
  point P33 (16.5436, 54.1504)
  point P34 (15.5245, 55.5154)
  dimension "d3" = 7
  dimension "d11" = 35
  dimension "d14" = 8
  dimension "d15" = 135
  dimension "d16" = 8
  dimension "d21" = 135
  dimension "d22" = 8
  dimension "d23" = 8
  dimension "d68" = 22
  dimension "d69" = 45
  dimension "d70" = 45
  dimension "d71" = 45
  dimension "d72" = 22.5
  dimension "d73" = 22.5
  dimension "d113" = 180
  dimension "d114" = 0
  dimension "d115" = 0
  dimension "d116" = 0.6
  dimension "d117" = 2.5
  dimension "d118" = 0
  dimension "d119" = 0
  dimension "d120" = 0.6
  dimension "d121" = 2.5
  dimension "d122" = 0.4
  dimension "d123" = 0
  dimension "d124" = 0
  dimension "d125" = 0
  dimension "d126" = 0.6
  dimension "d127" = 2.5
  dimension "d129" = 0
  dimension "d131" = 0.4
  dimension "d132" = 0.4
  constraints: 72 end point, 5 parallel, 3 midpoint, 80 other
  measures "d113" angle of L4 L2
  measures "d114" distance of point (16.87, 54.715) point (16.87, 54.715)
  measures "d115" distance of point (16.87, 54.715) point (16.87, 54.715)
  measures "d116" distance between parallel lines of L10 L14
  measures "d117" distance of L9.end L5.start
  measures "d118" distance of point (16.87, 51.985) point (16.87, 51.985)
  measures "d119" distance of point (16.87, 51.985) point (16.87, 51.985)
  measures "d120" distance between parallel lines of L22 L26
  measures "d121" distance of L22.start L17.start
  measures "d122" distance between parallel lines of L14 L23
  measures "d123" horizontal distance of point (16.87, 54.15) point (16.87, 52.55)
  measures "d124" distance of point (14.505, 53.35) point (14.505, 53.35)
  measures "d125" distance of point (14.505, 53.35) point (14.505, 53.35)
  measures "d126" distance between parallel lines of L34 L38
  measures "d127" distance of L33.end L29.start
  measures "d129" horizontal distance of point (14.505, 50.112) point (14.505, 51.185)
  measures "d131" distance between parallel lines of L15 L36
  measures "d132" distance between parallel lines of L37 L28
extrude "Extrusion10" cut sketch "Sketch17" against normal blind 1 contours L5 L28 L15 L14 L37 L10 | L28 L27 L38 L17 L18 L5 | L5 L18 L15 L28 | L37 L14 L33 L10 | L10 L33 L34 L27 L38 L37 | L5 L6 L35 L16 L15 L18 | L15 L18 L19 L36 L23 L28 | L33 L14 L13 L24 L9 L10 | L37 L36 L23 L32 L33 L14 | L27 L34 L17 L38 | L35 L40 L39 L38 L17 L34 L29 L30 L31 L6 | L6 L31 L16 L35 | L27 L26 L25 L24 L9 L20 L21 L22 L17 L34 | L36 L19 L32 L23 | L24 L13 L20 L9 | L6 L7 L8 L9 L20 L13 L12 L11 L16 L31 | L16 L31 L32 L19 L36 L35 | L32 L19 L20 L13 L24 L23 | S0 L41 S1 L42 S2 L43 S3 S4 S5 | S10 S11 L50 S12 S13 L51 | S14 S15 S16 S17 | S22 S23 S24 S25 S26 S27 S28 S29 S30 S31 | S32 S33 S34 S35 S36 S37 S38 S39 S40 S41 S42 S43 | S44 S45 S46 S47 | S52 S53 S54 S55 S56 S57 S58 S59 S60 S61 | S62 S63 L52 S64 S65 L53 | S66 S67 L54 S68 S69 L55 | S70 L56 L57 S71 S72 L58 L59 S73 S74 L60 S75 | S76 L61 S77 L62 S78 L63 S79
body "Solid1"
